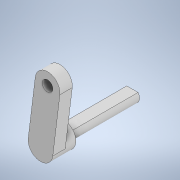
# Autodesk Inventor part: transmision_motor
Saved by Autodesk Inventor 2021 (Build 250183000, 183)
## iProperties
Created: 2026-05-04
Part Number: transmision_motor
Material: Genérico
Document SubType Name: Modeling
Designer: thepr
Density: 1 g/cm^3
Appearance: Valor por defecto
Author: thepr
## iProperties of the stored document _3DPrint.ipt
Created: 2026-05-08
Part Number: _3DPrint
Material: Genérico
Document SubType Name: Modeling
Designer: thepr
Density: 1 g/cm^3
Appearance: Valor por defecto
Author: thepr
Autodesk Inventor part; units mm, degrees
ref_plane "YZ Plane" through (0, 0, 0) normal (1, 0, 0) x (0, 1, 0)
ref_plane "XZ Plane" through (0, 0, 0) normal (0, 1, 0) x (-1, 0, 0)
ref_plane "XY Plane" through (0, 0, 0) normal (0, 0, 1) x (1, 0, 0)
sketch "Boceto1" plane through (0, 0, 0) normal (0, 0, 1) x (1, 0, 0)
  circle A0 centre (0, 0) radius 2
  circle A1 centre (0, 0) radius 3.5
  circle A2 centre (2, 16) radius 3.5
  line L0 (-3.473, 0.4341) -> (-1.473, 16.4341)
  line L1 (3.473, -0.4341) -> (5.473, 15.5659)
  circle A3 centre (2, 16) radius 1.5
  dimension "d0" = 4
  dimension "d2" = 7
  dimension "d3" = 7
  dimension "d4" = 2
  dimension "d5" = 16
  dimension "d12" = 3
  constraints: 4 centre point, 4 end point, 4 point on circle, 4 tangent, 3 coincident
  measures "d0" diameter of A0
  measures "d2" diameter of A1
  measures "d3" diameter of A2
  measures "d4" horizontal distance of point (0, 0) A2.centre
  measures "d5" vertical distance of point (0, 0) A2.centre
  measures "d12" diameter of A3
extrude "Extrusión1" add sketch "Boceto1" against normal blind 10 contours A0
extrude "Extrusión2" add sketch "Boceto1" along normal blind 2.5 contours A0 | A1 | A1 L0 A2 L1 | A2 | A3
extrude "Extrusión3" cut sketch "Boceto1" along normal blind 3 contours A3
sketch "Boceto2" plane through (0, 0, 0) normal (0, 0, -1) x (-1, 0, 0)
  arc A0 (-3.473, -0.4341) -> (3.473, 0.4341) centre (0, 0) ccw projected
  circle A1 centre (0, 0) radius 3.5
  point P0 (3.473, 0.4341)
  point P1 (-3.473, -0.4341)
  constraints: 1 centre point, 1 coincident, 1 concentric
extrude "Extrusión4" add sketch "Boceto2" along normal blind 4
sketch "Boceto3" plane through (0, 0, -10) normal (0, 0, -1) x (-1, 0, 0)
  circle A0 centre (0, 0) radius 2 projected
  circle A1 centre (0, 0) radius 2 projected
  line L0 (-1.6, 1.2) -> (1.6, 1.2)
  point P0 (-1.6, 1.2)
  point P1 (1.6, 1.2)
  dimension "d15" = 1.2
  constraints: 2 end point, 2 point on circle, 1 horizontal
  measures "d15" distance from line of point (0, 0) L0
extrude "Extrusión5" cut sketch "Boceto3" against normal blind 5 contours L0 A0 picked at (0.4272, 1.3118)
move faces "Desplazar1" translate (0, 0, -1) faces at (-0.7371, 11.5147, 0)
move faces "Desplazar2" translate (0, 0, -3) faces at (-0.0567, 0.1358, -10)
move faces "Desplazar3" translate (0, 0, -10.5) faces at (-0.0567, 0.1358, -13)
